Autodesk Fusion 360 part; units mm, degrees
(part 4 of 5)
sketch "Condenser contact rib sketch" plane through (0, 0, 1004) normal (0, 0, 1) x (1, 0, 0) in component "MM16 Upward-facing radiator panel"
  line L0 (-680, -282) -> (680, -282)
  line L1 (680, -282) -> (680, -258)
  line L2 (680, -258) -> (-680, -258)
  line L3 (-680, -258) -> (-680, -282)
extrude "Condenser contact rib" add sketch "Condenser contact rib sketch" along normal blind 14 bodies 194 in component "MM16 Upward-facing radiator panel"
ref_plane "WorkPlane7" through (-681, 0, 0) normal (1, 0, 0) x (0, 1, 0) in component "MM16 Upward-facing radiator panel"
sketch "Heat pipe contact groove sketch" plane through (-681, 0, 0) normal (1, 0, 0) x (0, 0, -1) in component "MM16 Upward-facing radiator panel"
  circle A0 centre (-1012, -270) radius 6
extrude "Heat pipe contact groove" cut sketch "Heat pipe contact groove sketch" along normal blind 1362 bodies 194 in component "MM16 Upward-facing radiator panel"
ref_plane "WorkPlane8" through (0, 0, 1004) normal (0, 0, 1) x (1, 0, 0) in component "MM16 Upward-facing radiator panel"
sketch "Condenser contact rib sketch (1)" plane through (0, 0, 1004) normal (0, 0, 1) x (1, 0, 0) in component "MM16 Upward-facing radiator panel"
  line L0 (-680, -102) -> (680, -102)
  line L1 (680, -102) -> (680, -78)
  line L2 (680, -78) -> (-680, -78)
  line L3 (-680, -78) -> (-680, -102)
extrude "Condenser contact rib (1)" add sketch "Condenser contact rib sketch (1)" along normal blind 14 bodies 194 in component "MM16 Upward-facing radiator panel"
ref_plane "WorkPlane9" through (-681, 0, 0) normal (1, 0, 0) x (0, 1, 0) in component "MM16 Upward-facing radiator panel"
sketch "Heat pipe contact groove sketch (1)" plane through (-681, 0, 0) normal (1, 0, 0) x (0, 0, -1) in component "MM16 Upward-facing radiator panel"
  circle A0 centre (-1012, -90) radius 6
extrude "Heat pipe contact groove (1)" cut sketch "Heat pipe contact groove sketch (1)" along normal blind 1362 bodies 194 in component "MM16 Upward-facing radiator panel"
ref_plane "WorkPlane10" through (0, 0, 1004) normal (0, 0, 1) x (1, 0, 0) in component "MM16 Upward-facing radiator panel"
sketch "Condenser contact rib sketch (2)" plane through (0, 0, 1004) normal (0, 0, 1) x (1, 0, 0) in component "MM16 Upward-facing radiator panel"
  line L0 (-680, 78) -> (680, 78)
  line L1 (680, 78) -> (680, 102)
  line L2 (680, 102) -> (-680, 102)
  line L3 (-680, 102) -> (-680, 78)
extrude "Condenser contact rib (2)" add sketch "Condenser contact rib sketch (2)" along normal blind 14 bodies 194 in component "MM16 Upward-facing radiator panel"
ref_plane "WorkPlane11" through (-681, 0, 0) normal (1, 0, 0) x (0, 1, 0) in component "MM16 Upward-facing radiator panel"
sketch "Heat pipe contact groove sketch (2)" plane through (-681, 0, 0) normal (1, 0, 0) x (0, 0, -1) in component "MM16 Upward-facing radiator panel"
  circle A0 centre (-1012, 90) radius 6
extrude "Heat pipe contact groove (2)" cut sketch "Heat pipe contact groove sketch (2)" along normal blind 1362 bodies 194 in component "MM16 Upward-facing radiator panel"
ref_plane "WorkPlane12" through (0, 0, 1004) normal (0, 0, 1) x (1, 0, 0) in component "MM16 Upward-facing radiator panel"
sketch "Condenser contact rib sketch (3)" plane through (0, 0, 1004) normal (0, 0, 1) x (1, 0, 0) in component "MM16 Upward-facing radiator panel"
  line L0 (-680, 258) -> (680, 258)
  line L1 (680, 258) -> (680, 282)
  line L2 (680, 282) -> (-680, 282)
  line L3 (-680, 282) -> (-680, 258)
extrude "Condenser contact rib (3)" add sketch "Condenser contact rib sketch (3)" along normal blind 14 bodies 194 in component "MM16 Upward-facing radiator panel"
ref_plane "WorkPlane13" through (-681, 0, 0) normal (1, 0, 0) x (0, 1, 0) in component "MM16 Upward-facing radiator panel"
sketch "Heat pipe contact groove sketch (3)" plane through (-681, 0, 0) normal (1, 0, 0) x (0, 0, -1) in component "MM16 Upward-facing radiator panel"
  circle A0 centre (-1012, 270) radius 6
extrude "Heat pipe contact groove (3)" cut sketch "Heat pipe contact groove sketch (3)" along normal blind 1362 bodies 194 in component "MM16 Upward-facing radiator panel"
ref_plane "WorkPlane14" through (0, 0, 1015) normal (0, 0, 1) x (1, 0, 0) in component "MM16 Upward-facing radiator panel"
sketch "Local fastener load spreader sketch" plane through (0, 0, 1015) normal (0, 0, 1) x (1, 0, 0) in component "MM16 Upward-facing radiator panel"
  line L0 (-680, -360) -> (-620, -360)
  line L1 (-620, -360) -> (-620, -300)
  line L2 (-620, -300) -> (-680, -300)
  line L3 (-680, -300) -> (-680, -360)
extrude "Local fastener load spreader" add sketch "Local fastener load spreader sketch" along normal blind 3 bodies 194 in component "MM16 Upward-facing radiator panel"
ref_plane "WorkPlane15" through (0, 0, 1015) normal (0, 0, 1) x (1, 0, 0) in component "MM16 Upward-facing radiator panel"
sketch "Local fastener load spreader sketch (1)" plane through (0, 0, 1015) normal (0, 0, 1) x (1, 0, 0) in component "MM16 Upward-facing radiator panel"
  line L0 (-680, 300) -> (-620, 300)
  line L1 (-620, 300) -> (-620, 360)
  line L2 (-620, 360) -> (-680, 360)
  line L3 (-680, 360) -> (-680, 300)
extrude "Local fastener load spreader (1)" add sketch "Local fastener load spreader sketch (1)" along normal blind 3 bodies 194 in component "MM16 Upward-facing radiator panel"
ref_plane "WorkPlane16" through (0, 0, 1015) normal (0, 0, 1) x (1, 0, 0) in component "MM16 Upward-facing radiator panel"
sketch "Local fastener load spreader sketch (2)" plane through (0, 0, 1015) normal (0, 0, 1) x (1, 0, 0) in component "MM16 Upward-facing radiator panel"
  line L0 (620, -360) -> (680, -360)
  line L1 (680, -360) -> (680, -300)
  line L2 (680, -300) -> (620, -300)
  line L3 (620, -300) -> (620, -360)
extrude "Local fastener load spreader (2)" add sketch "Local fastener load spreader sketch (2)" along normal blind 3 bodies 194 in component "MM16 Upward-facing radiator panel"
ref_plane "WorkPlane17" through (0, 0, 1015) normal (0, 0, 1) x (1, 0, 0) in component "MM16 Upward-facing radiator panel"
sketch "Local fastener load spreader sketch (3)" plane through (0, 0, 1015) normal (0, 0, 1) x (1, 0, 0) in component "MM16 Upward-facing radiator panel"
  line L0 (620, 300) -> (680, 300)
  line L1 (680, 300) -> (680, 360)
  line L2 (680, 360) -> (620, 360)
  line L3 (620, 360) -> (620, 300)
extrude "Local fastener load spreader (3)" add sketch "Local fastener load spreader sketch (3)" along normal blind 3 bodies 194 in component "MM16 Upward-facing radiator panel"
ref_plane "WorkPlane1" through (-672, 0, 0) normal (1, 0, 0) x (0, 1, 0) in component "MM46 Radiator four-standoff mounting set"
sketch "Sketch1" plane through (-672, 0, 0) normal (1, 0, 0) x (0, 0, -1) in component "MM46 Radiator four-standoff mounting set"
  arc A0 (-893.7271, -291.2934) -> (-864.9383, -368.0784) centre (0, 0) ccw
  arc A1 (-899.4317, -293.1527) -> (-870.4592, -370.4278) centre (0, 0) ccw
  line L0 (-893.7271, -291.2934) -> (-899.4317, -293.1527)
  line L1 (-864.9383, -368.0784) -> (-870.4592, -370.4278)
extrude "Conformal load-band foot" add sketch "Sketch1" along normal blind 44 separate body makes body 195 in component "MM46 Radiator four-standoff mounting set"
ref_plane "WorkPlane2" through (0, 0, 850) normal (0, 0, 1) x (1, 0, 0) in component "MM46 Radiator four-standoff mounting set"
sketch "Thin-wall support neck sketch" plane through (0, 0, 850) normal (0, 0, 1) x (1, 0, 0) in component "MM46 Radiator four-standoff mounting set"
  line L0 (-655, -338) -> (-645, -338)
  line L1 (-645, -338) -> (-645, -322)
  line L2 (-645, -322) -> (-655, -322)
  line L3 (-655, -322) -> (-655, -338)
  line L4 (-654.4, -337.4) -> (-645.6, -337.4)
  line L5 (-645.6, -337.4) -> (-645.6, -322.6)
  line L6 (-645.6, -322.6) -> (-654.4, -322.6)
  line L7 (-654.4, -322.6) -> (-654.4, -337.4)
extrude "Thin-wall support neck" add sketch "Thin-wall support neck sketch" along normal blind 159 bodies 195 in component "MM46 Radiator four-standoff mounting set"
ref_plane "WorkPlane3" through (0, 0, 1009) normal (0, 0, 1) x (1, 0, 0) in component "MM46 Radiator four-standoff mounting set"
sketch "Panel bearing flange sketch" plane through (0, 0, 1009) normal (0, 0, 1) x (1, 0, 0) in component "MM46 Radiator four-standoff mounting set"
  line L0 (-675, -355) -> (-625, -355)
  line L1 (-625, -355) -> (-625, -305)
  line L2 (-625, -305) -> (-675, -305)
  line L3 (-675, -305) -> (-675, -355)
extrude "Panel bearing flange" add sketch "Panel bearing flange sketch" along normal blind 6 bodies 195 in component "MM46 Radiator four-standoff mounting set"
ref_plane "WorkPlane7" through (0, 0, 865) normal (0, 0, 1) x (1, 0, 0) in component "MM07 MLI blanket envelope"
sketch "Radiator support blanket clearance sketch" plane through (0, 0, 865) normal (0, 0, 1) x (1, 0, 0) in component "MM07 MLI blanket envelope"
  line L0 (-677, -385) -> (-623, -385)
  line L1 (-623, -385) -> (-623, -275)
  line L2 (-623, -275) -> (-677, -275)
  line L3 (-677, -275) -> (-677, -385)
extrude "Radiator support blanket clearance" cut sketch "Radiator support blanket clearance sketch" along normal blind 160 bodies 13 in component "MM07 MLI blanket envelope"
ref_plane "WorkPlane4" through (-672, 0, 0) normal (1, 0, 0) x (0, 1, 0) in component "MM46 Radiator four-standoff mounting set"
sketch "Sketch4 (2)" plane through (-672, 0, 0) normal (1, 0, 0) x (0, 0, -1) in component "MM46 Radiator four-standoff mounting set"
  arc A0 (-864.9383, 368.0784) -> (-893.7271, 291.2934) centre (0, 0) ccw
  arc A1 (-870.4592, 370.4278) -> (-899.4317, 293.1527) centre (0, 0) ccw
  line L0 (-864.9383, 368.0784) -> (-870.4592, 370.4278)
  line L1 (-893.7271, 291.2934) -> (-899.4317, 293.1527)
extrude "Conformal load-band foot (1)" add sketch "Sketch4 (2)" along normal blind 44 separate body makes body 196 in component "MM46 Radiator four-standoff mounting set"
ref_plane "WorkPlane5" through (0, 0, 850) normal (0, 0, 1) x (1, 0, 0) in component "MM46 Radiator four-standoff mounting set"
sketch "Thin-wall support neck sketch (1)" plane through (0, 0, 850) normal (0, 0, 1) x (1, 0, 0) in component "MM46 Radiator four-standoff mounting set"
  line L0 (-655, 322) -> (-645, 322)
  line L1 (-645, 322) -> (-645, 338)
  line L2 (-645, 338) -> (-655, 338)
  line L3 (-655, 338) -> (-655, 322)
  line L4 (-654.4, 322.6) -> (-645.6, 322.6)
  line L5 (-645.6, 322.6) -> (-645.6, 337.4)
  line L6 (-645.6, 337.4) -> (-654.4, 337.4)
  line L7 (-654.4, 337.4) -> (-654.4, 322.6)
extrude "Thin-wall support neck (1)" add sketch "Thin-wall support neck sketch (1)" along normal blind 159 bodies 196 in component "MM46 Radiator four-standoff mounting set"
ref_plane "WorkPlane6" through (0, 0, 1009) normal (0, 0, 1) x (1, 0, 0) in component "MM46 Radiator four-standoff mounting set"
sketch "Panel bearing flange sketch (1)" plane through (0, 0, 1009) normal (0, 0, 1) x (1, 0, 0) in component "MM46 Radiator four-standoff mounting set"
  line L0 (-675, 305) -> (-625, 305)
  line L1 (-625, 305) -> (-625, 355)
  line L2 (-625, 355) -> (-675, 355)
  line L3 (-675, 355) -> (-675, 305)
extrude "Panel bearing flange (1)" add sketch "Panel bearing flange sketch (1)" along normal blind 6 bodies 196 in component "MM46 Radiator four-standoff mounting set"
ref_plane "WorkPlane8" through (0, 0, 865) normal (0, 0, 1) x (1, 0, 0) in component "MM07 MLI blanket envelope"
sketch "Radiator support blanket clearance sketch (1)" plane through (0, 0, 865) normal (0, 0, 1) x (1, 0, 0) in component "MM07 MLI blanket envelope"
  line L0 (-677, 275) -> (-623, 275)
  line L1 (-623, 275) -> (-623, 385)
  line L2 (-623, 385) -> (-677, 385)
  line L3 (-677, 385) -> (-677, 275)
extrude "Radiator support blanket clearance (1)" cut sketch "Radiator support blanket clearance sketch (1)" along normal blind 160 bodies 13 in component "MM07 MLI blanket envelope"
ref_plane "WorkPlane7" through (628, 0, 0) normal (1, 0, 0) x (0, 1, 0) in component "MM46 Radiator four-standoff mounting set"
sketch "Sketch7 (2)" plane through (628, 0, 0) normal (1, 0, 0) x (0, 0, -1) in component "MM46 Radiator four-standoff mounting set"
  arc A0 (-893.7271, -291.2934) -> (-864.9383, -368.0784) centre (0, 0) ccw
  arc A1 (-899.4317, -293.1527) -> (-870.4592, -370.4278) centre (0, 0) ccw
  line L0 (-893.7271, -291.2934) -> (-899.4317, -293.1527)
  line L1 (-864.9383, -368.0784) -> (-870.4592, -370.4278)
extrude "Conformal load-band foot (2)" add sketch "Sketch7 (2)" along normal blind 44 separate body makes body 197 in component "MM46 Radiator four-standoff mounting set"
ref_plane "WorkPlane8" through (0, 0, 850) normal (0, 0, 1) x (1, 0, 0) in component "MM46 Radiator four-standoff mounting set"
sketch "Thin-wall support neck sketch (2)" plane through (0, 0, 850) normal (0, 0, 1) x (1, 0, 0) in component "MM46 Radiator four-standoff mounting set"
  line L0 (645, -338) -> (655, -338)
  line L1 (655, -338) -> (655, -322)
  line L2 (655, -322) -> (645, -322)
  line L3 (645, -322) -> (645, -338)
  line L4 (645.6, -337.4) -> (654.4, -337.4)
  line L5 (654.4, -337.4) -> (654.4, -322.6)
  line L6 (654.4, -322.6) -> (645.6, -322.6)
  line L7 (645.6, -322.6) -> (645.6, -337.4)
extrude "Thin-wall support neck (2)" add sketch "Thin-wall support neck sketch (2)" along normal blind 159 bodies 197 in component "MM46 Radiator four-standoff mounting set"
ref_plane "WorkPlane9" through (0, 0, 1009) normal (0, 0, 1) x (1, 0, 0) in component "MM46 Radiator four-standoff mounting set"
sketch "Panel bearing flange sketch (2)" plane through (0, 0, 1009) normal (0, 0, 1) x (1, 0, 0) in component "MM46 Radiator four-standoff mounting set"
  line L0 (625, -355) -> (675, -355)
  line L1 (675, -355) -> (675, -305)
  line L2 (675, -305) -> (625, -305)
  line L3 (625, -305) -> (625, -355)
extrude "Panel bearing flange (2)" add sketch "Panel bearing flange sketch (2)" along normal blind 6 bodies 197 in component "MM46 Radiator four-standoff mounting set"
ref_plane "WorkPlane9" through (0, 0, 865) normal (0, 0, 1) x (1, 0, 0) in component "MM07 MLI blanket envelope"
sketch "Radiator support blanket clearance sketch (2)" plane through (0, 0, 865) normal (0, 0, 1) x (1, 0, 0) in component "MM07 MLI blanket envelope"
  line L0 (623, -385) -> (677, -385)
  line L1 (677, -385) -> (677, -275)
  line L2 (677, -275) -> (623, -275)
  line L3 (623, -275) -> (623, -385)
extrude "Radiator support blanket clearance (2)" cut sketch "Radiator support blanket clearance sketch (2)" along normal blind 160 bodies 13 in component "MM07 MLI blanket envelope"
ref_plane "WorkPlane10" through (628, 0, 0) normal (1, 0, 0) x (0, 1, 0) in component "MM46 Radiator four-standoff mounting set"
sketch "Sketch10 (2)" plane through (628, 0, 0) normal (1, 0, 0) x (0, 0, -1) in component "MM46 Radiator four-standoff mounting set"
  arc A0 (-864.9383, 368.0784) -> (-893.7271, 291.2934) centre (0, 0) ccw
  arc A1 (-870.4592, 370.4278) -> (-899.4317, 293.1527) centre (0, 0) ccw
  line L0 (-864.9383, 368.0784) -> (-870.4592, 370.4278)
  line L1 (-893.7271, 291.2934) -> (-899.4317, 293.1527)
extrude "Conformal load-band foot (3)" add sketch "Sketch10 (2)" along normal blind 44 separate body makes body 198 in component "MM46 Radiator four-standoff mounting set"
ref_plane "WorkPlane11" through (0, 0, 850) normal (0, 0, 1) x (1, 0, 0) in component "MM46 Radiator four-standoff mounting set"
sketch "Thin-wall support neck sketch (3)" plane through (0, 0, 850) normal (0, 0, 1) x (1, 0, 0) in component "MM46 Radiator four-standoff mounting set"
  line L0 (645, 322) -> (655, 322)
  line L1 (655, 322) -> (655, 338)
  line L2 (655, 338) -> (645, 338)
  line L3 (645, 338) -> (645, 322)
  line L4 (645.6, 322.6) -> (654.4, 322.6)
  line L5 (654.4, 322.6) -> (654.4, 337.4)
  line L6 (654.4, 337.4) -> (645.6, 337.4)
  line L7 (645.6, 337.4) -> (645.6, 322.6)
extrude "Thin-wall support neck (3)" add sketch "Thin-wall support neck sketch (3)" along normal blind 159 bodies 198 in component "MM46 Radiator four-standoff mounting set"
ref_plane "WorkPlane12" through (0, 0, 1009) normal (0, 0, 1) x (1, 0, 0) in component "MM46 Radiator four-standoff mounting set"
sketch "Panel bearing flange sketch (3)" plane through (0, 0, 1009) normal (0, 0, 1) x (1, 0, 0) in component "MM46 Radiator four-standoff mounting set"
  line L0 (625, 305) -> (675, 305)
  line L1 (675, 305) -> (675, 355)
  line L2 (675, 355) -> (625, 355)
  line L3 (625, 355) -> (625, 305)
extrude "Panel bearing flange (3)" add sketch "Panel bearing flange sketch (3)" along normal blind 6 bodies 198 in component "MM46 Radiator four-standoff mounting set"
ref_plane "WorkPlane10" through (0, 0, 865) normal (0, 0, 1) x (1, 0, 0) in component "MM07 MLI blanket envelope"
sketch "Radiator support blanket clearance sketch (3)" plane through (0, 0, 865) normal (0, 0, 1) x (1, 0, 0) in component "MM07 MLI blanket envelope"
  line L0 (623, 275) -> (677, 275)
  line L1 (677, 275) -> (677, 385)
  line L2 (677, 385) -> (623, 385)
  line L3 (623, 385) -> (623, 275)
extrude "Radiator support blanket clearance (3)" cut sketch "Radiator support blanket clearance sketch (3)" along normal blind 160 bodies 13 in component "MM07 MLI blanket envelope"
ref_plane "WorkPlane13" through (-700, 0, 0) normal (1, 0, 0) x (0, 1, 0) in component "MM46 Radiator four-standoff mounting set"
sketch "Bearing clearance to band outside sketch" plane through (-700, 0, 0) normal (1, 0, 0) x (0, 0, -1) in component "MM46 Radiator four-standoff mounting set"
  circle A0 centre (0, 0) radius 940
extrude "Bearing clearance to band outside" cut sketch "Bearing clearance to band outside sketch" along normal blind 1400 bodies 195 196 197 198 in component "MM46 Radiator four-standoff mounting set"
ref_plane "WorkPlane1" through (-750, 0, 0) normal (1, 0, 0) x (0, 1, 0) in component "MM17 Four regulated heat-pipe and collector sets"
sketch "Outer pressure-wall collector sketch" plane through (-750, 0, 0) normal (1, 0, 0) x (0, 0, -1) in component "MM17 Four regulated heat-pipe and collector sets"
  arc A0 (-899.3104, -207.7734) -> (-861.6419, -330.9112) centre (0, 0) ccw
  arc A1 (-900.7719, -208.1111) -> (-863.0422, -331.449) centre (0, 0) ccw
  line L0 (-899.3104, -207.7734) -> (-900.7719, -208.1111)
  line L1 (-861.6419, -330.9112) -> (-863.0422, -331.449)
extrude "Outer pressure-wall collector" add sketch "Outer pressure-wall collector sketch" along normal blind 60 separate body makes body 199 in component "MM17 Four regulated heat-pipe and collector sets"
ref_plane "WorkPlane2" through (0, -270, 0) normal (0, 1, 0) x (0, 0, 1) in component "MM17 Four regulated heat-pipe and collector sets"
sketch "Regulated heat pipe centreline" plane through (0, -270, 0) normal (0, 1, 0) x (1, 0, 0) in component "MM17 Four regulated heat-pipe and collector sets"
  line L0 (-720, -875.6262) -> (-720, -992)
  arc A0 (-720, -992) -> (-700, -1012) centre (-700, -992) ccw
  line L1 (-700, -1012) -> (710, -1012)
ref_plane "WorkPlane3" through (0, 0, 875.6262) normal (0, 0, 1) x (1, 0, 0) in component "MM17 Four regulated heat-pipe and collector sets"
sketch "Twelve millimetre heat pipe wall" plane through (0, 0, 875.6262) normal (0, 0, 1) x (1, 0, 0) in component "MM17 Four regulated heat-pipe and collector sets"
  circle A0 centre (-720, -270) radius 6
  circle A1 centre (-720, -270) radius 5.5
sweep "Closed heat pipe envelope" add profiles "Twelve millimetre heat pipe wall" path "Regulated heat pipe centreline" along L0 A0 L1 section 1 bodies 199 in component "MM17 Four regulated heat-pipe and collector sets"
ref_plane "WorkPlane4" through (709.5, 0, 0) normal (1, 0, 0) x (0, 1, 0) in component "MM17 Four regulated heat-pipe and collector sets"
sketch "Condenser end cap sketch" plane through (709.5, 0, 0) normal (1, 0, 0) x (0, 0, -1) in component "MM17 Four regulated heat-pipe and collector sets"
  circle A0 centre (-1012, -270) radius 6
extrude "Condenser end cap" add sketch "Condenser end cap sketch" along normal blind 0.5 separate body makes body 200 in component "MM17 Four regulated heat-pipe and collector sets"
ref_plane "WorkPlane5" through (0, 0, 990) normal (0, 0, 1) x (1, 0, 0) in component "MM17 Four regulated heat-pipe and collector sets"
sketch "Gas reservoir connecting neck sketch" plane through (0, 0, 990) normal (0, 0, 1) x (1, 0, 0) in component "MM17 Four regulated heat-pipe and collector sets"
  circle A0 centre (710, -270) radius 3.5
  circle A1 centre (710, -270) radius 2.5
extrude "Gas reservoir connecting neck" add sketch "Gas reservoir connecting neck sketch" along normal blind 22 bodies 200 in component "MM17 Four regulated heat-pipe and collector sets"
ref_plane "WorkPlane6" through (695, 0, 0) normal (1, 0, 0) x (0, 1, 0) in component "MM17 Four regulated heat-pipe and collector sets"
sketch "Control gas reservoir envelope sketch" plane through (695, 0, 0) normal (1, 0, 0) x (0, 0, -1) in component "MM17 Four regulated heat-pipe and collector sets"
  circle A0 centre (-990, -270) radius 10
  circle A1 centre (-990, -270) radius 9.5
extrude "Control gas reservoir envelope" add sketch "Control gas reservoir envelope sketch" along normal blind 30 bodies 200 in component "MM17 Four regulated heat-pipe and collector sets"
ref_plane "WorkPlane7" through (695, 0, 0) normal (1, 0, 0) x (0, 1, 0) in component "MM17 Four regulated heat-pipe and collector sets"
sketch "Reservoir end closure sketch" plane through (695, 0, 0) normal (1, 0, 0) x (0, 0, -1) in component "MM17 Four regulated heat-pipe and collector sets"
  circle A0 centre (-990, -270) radius 10
extrude "Reservoir end closure" add sketch "Reservoir end closure sketch" along normal blind 0.5 bodies 200 in component "MM17 Four regulated heat-pipe and collector sets"
ref_plane "WorkPlane8" through (724.5, 0, 0) normal (1, 0, 0) x (0, 1, 0) in component "MM17 Four regulated heat-pipe and collector sets"
sketch "Reservoir end closure sketch (1)" plane through (724.5, 0, 0) normal (1, 0, 0) x (0, 0, -1) in component "MM17 Four regulated heat-pipe and collector sets"
  circle A0 centre (-990, -270) radius 10
extrude "Reservoir end closure (1)" add sketch "Reservoir end closure sketch (1)" along normal blind 0.5 bodies 200 in component "MM17 Four regulated heat-pipe and collector sets"
ref_plane "WorkPlane11" through (0, 0, 872) normal (0, 0, 1) x (1, 0, 0) in component "MM07 MLI blanket envelope"
sketch "Thermal collector blanket clearance sketch" plane through (0, 0, 872) normal (0, 0, 1) x (1, 0, 0) in component "MM07 MLI blanket envelope"
  line L0 (-755, -350) -> (-685, -350)
  line L1 (-685, -350) -> (-685, -190)
  line L2 (-685, -190) -> (-755, -190)
  line L3 (-755, -190) -> (-755, -350)
extrude "Thermal collector blanket clearance" cut sketch "Thermal collector blanket clearance sketch" along normal blind 150 bodies 13 in component "MM07 MLI blanket envelope"
ref_plane "WorkPlane9" through (690, 0, 0) normal (1, 0, 0) x (0, 1, 0) in component "MM17 Four regulated heat-pipe and collector sets"
sketch "Outer pressure-wall collector sketch (1)" plane through (690, 0, 0) normal (1, 0, 0) x (0, 0, -1) in component "MM17 Four regulated heat-pipe and collector sets"
  arc A0 (-922.6421, -25.7024) -> (-910.0859, -153.8592) centre (0, 0) ccw
  arc A1 (-924.1415, -25.7441) -> (-911.5649, -154.1092) centre (0, 0) ccw
  line L0 (-922.6421, -25.7024) -> (-924.1415, -25.7441)
  line L1 (-910.0859, -153.8592) -> (-911.5649, -154.1092)
extrude "Outer pressure-wall collector (1)" add sketch "Outer pressure-wall collector sketch (1)" along normal blind 60 separate body makes body 201 in component "MM17 Four regulated heat-pipe and collector sets"
ref_plane "WorkPlane10" through (0, -90, 0) normal (0, 1, 0) x (0, 0, 1) in component "MM17 Four regulated heat-pipe and collector sets"
sketch "Regulated heat pipe centreline (1)" plane through (0, -90, 0) normal (0, 1, 0) x (1, 0, 0) in component "MM17 Four regulated heat-pipe and collector sets"
  line L0 (720, -911.6017) -> (720, -992)
  arc A0 (700, -1012) -> (720, -992) centre (700, -992) ccw
  line L1 (700, -1012) -> (-710, -1012)
ref_plane "WorkPlane11" through (0, 0, 911.6017) normal (0, 0, 1) x (1, 0, 0) in component "MM17 Four regulated heat-pipe and collector sets"
sketch "Twelve millimetre heat pipe wall (1)" plane through (0, 0, 911.6017) normal (0, 0, 1) x (1, 0, 0) in component "MM17 Four regulated heat-pipe and collector sets"
  circle A0 centre (720, -90) radius 6
  circle A1 centre (720, -90) radius 5.5
sweep "Closed heat pipe envelope (1)" add profiles "Twelve millimetre heat pipe wall (1)" path "Regulated heat pipe centreline (1)" along L0 A0 L1 section 1 bodies 201 in component "MM17 Four regulated heat-pipe and collector sets"
ref_plane "WorkPlane12" through (-710, 0, 0) normal (1, 0, 0) x (0, 1, 0) in component "MM17 Four regulated heat-pipe and collector sets"
sketch "Condenser end cap sketch (1)" plane through (-710, 0, 0) normal (1, 0, 0) x (0, 0, -1) in component "MM17 Four regulated heat-pipe and collector sets"
  circle A0 centre (-1012, -90) radius 6
extrude "Condenser end cap (1)" add sketch "Condenser end cap sketch (1)" along normal blind 0.5 separate body makes body 202 in component "MM17 Four regulated heat-pipe and collector sets"
ref_plane "WorkPlane13" through (0, 0, 990) normal (0, 0, 1) x (1, 0, 0) in component "MM17 Four regulated heat-pipe and collector sets"
sketch "Gas reservoir connecting neck sketch (1)" plane through (0, 0, 990) normal (0, 0, 1) x (1, 0, 0) in component "MM17 Four regulated heat-pipe and collector sets"
  circle A0 centre (-710, -90) radius 3.5
  circle A1 centre (-710, -90) radius 2.5
extrude "Gas reservoir connecting neck (1)" add sketch "Gas reservoir connecting neck sketch (1)" along normal blind 22 bodies 202 in component "MM17 Four regulated heat-pipe and collector sets"
ref_plane "WorkPlane14" through (-725, 0, 0) normal (1, 0, 0) x (0, 1, 0) in component "MM17 Four regulated heat-pipe and collector sets"
sketch "Control gas reservoir envelope sketch (1)" plane through (-725, 0, 0) normal (1, 0, 0) x (0, 0, -1) in component "MM17 Four regulated heat-pipe and collector sets"
  circle A0 centre (-990, -90) radius 10
  circle A1 centre (-990, -90) radius 9.5
extrude "Control gas reservoir envelope (1)" add sketch "Control gas reservoir envelope sketch (1)" along normal blind 30 bodies 202 in component "MM17 Four regulated heat-pipe and collector sets"
ref_plane "WorkPlane15" through (-725, 0, 0) normal (1, 0, 0) x (0, 1, 0) in component "MM17 Four regulated heat-pipe and collector sets"
sketch "Reservoir end closure sketch (2)" plane through (-725, 0, 0) normal (1, 0, 0) x (0, 0, -1) in component "MM17 Four regulated heat-pipe and collector sets"
  circle A0 centre (-990, -90) radius 10
extrude "Reservoir end closure (2)" add sketch "Reservoir end closure sketch (2)" along normal blind 0.5 bodies 202 in component "MM17 Four regulated heat-pipe and collector sets"
ref_plane "WorkPlane16" through (-695.5, 0, 0) normal (1, 0, 0) x (0, 1, 0) in component "MM17 Four regulated heat-pipe and collector sets"
sketch "Reservoir end closure sketch (3)" plane through (-695.5, 0, 0) normal (1, 0, 0) x (0, 0, -1) in component "MM17 Four regulated heat-pipe and collector sets"
  circle A0 centre (-990, -90) radius 10
extrude "Reservoir end closure (3)" add sketch "Reservoir end closure sketch (3)" along normal blind 0.5 bodies 202 in component "MM17 Four regulated heat-pipe and collector sets"
ref_plane "WorkPlane12" through (0, 0, 872) normal (0, 0, 1) x (1, 0, 0) in component "MM07 MLI blanket envelope"
sketch "Thermal collector blanket clearance sketch (1)" plane through (0, 0, 872) normal (0, 0, 1) x (1, 0, 0) in component "MM07 MLI blanket envelope"
  line L0 (685, -170) -> (755, -170)
  line L1 (755, -170) -> (755, -10)
  line L2 (755, -10) -> (685, -10)
  line L3 (685, -10) -> (685, -170)
extrude "Thermal collector blanket clearance (1)" cut sketch "Thermal collector blanket clearance sketch (1)" along normal blind 150 bodies 13 in component "MM07 MLI blanket envelope"
ref_plane "WorkPlane17" through (-750, 0, 0) normal (1, 0, 0) x (0, 1, 0) in component "MM17 Four regulated heat-pipe and collector sets"
sketch "Outer pressure-wall collector sketch (2)" plane through (-750, 0, 0) normal (1, 0, 0) x (0, 0, -1) in component "MM17 Four regulated heat-pipe and collector sets"
  arc A0 (-910.0859, 153.8592) -> (-922.6421, 25.7024) centre (0, 0) ccw
  arc A1 (-911.5649, 154.1092) -> (-924.1415, 25.7441) centre (0, 0) ccw
  line L0 (-910.0859, 153.8592) -> (-911.5649, 154.1092)
  line L1 (-922.6421, 25.7024) -> (-924.1415, 25.7441)
extrude "Outer pressure-wall collector (2)" add sketch "Outer pressure-wall collector sketch (2)" along normal blind 60 separate body makes body 203 in component "MM17 Four regulated heat-pipe and collector sets"
ref_plane "WorkPlane18" through (0, 90, 0) normal (0, 1, 0) x (0, 0, 1) in component "MM17 Four regulated heat-pipe and collector sets"
sketch "Regulated heat pipe centreline (2)" plane through (0, 90, 0) normal (0, 1, 0) x (1, 0, 0) in component "MM17 Four regulated heat-pipe and collector sets"
  line L0 (-720, -911.6017) -> (-720, -992)
  arc A0 (-720, -992) -> (-700, -1012) centre (-700, -992) ccw
  line L1 (-700, -1012) -> (710, -1012)
ref_plane "WorkPlane19" through (0, 0, 911.6017) normal (0, 0, 1) x (1, 0, 0) in component "MM17 Four regulated heat-pipe and collector sets"
sketch "Twelve millimetre heat pipe wall (2)" plane through (0, 0, 911.6017) normal (0, 0, 1) x (1, 0, 0) in component "MM17 Four regulated heat-pipe and collector sets"
  circle A0 centre (-720, 90) radius 6
  circle A1 centre (-720, 90) radius 5.5
sweep "Closed heat pipe envelope (2)" add profiles "Twelve millimetre heat pipe wall (2)" path "Regulated heat pipe centreline (2)" along L0 A0 L1 section 1 bodies 203 in component "MM17 Four regulated heat-pipe and collector sets"
ref_plane "WorkPlane20" through (709.5, 0, 0) normal (1, 0, 0) x (0, 1, 0) in component "MM17 Four regulated heat-pipe and collector sets"
sketch "Condenser end cap sketch (2)" plane through (709.5, 0, 0) normal (1, 0, 0) x (0, 0, -1) in component "MM17 Four regulated heat-pipe and collector sets"
  circle A0 centre (-1012, 90) radius 6
extrude "Condenser end cap (2)" add sketch "Condenser end cap sketch (2)" along normal blind 0.5 separate body makes body 204 in component "MM17 Four regulated heat-pipe and collector sets"
ref_plane "WorkPlane21" through (0, 0, 990) normal (0, 0, 1) x (1, 0, 0) in component "MM17 Four regulated heat-pipe and collector sets"
sketch "Gas reservoir connecting neck sketch (2)" plane through (0, 0, 990) normal (0, 0, 1) x (1, 0, 0) in component "MM17 Four regulated heat-pipe and collector sets"
  circle A0 centre (710, 90) radius 3.5
  circle A1 centre (710, 90) radius 2.5
extrude "Gas reservoir connecting neck (2)" add sketch "Gas reservoir connecting neck sketch (2)" along normal blind 22 bodies 204 in component "MM17 Four regulated heat-pipe and collector sets"
ref_plane "WorkPlane22" through (695, 0, 0) normal (1, 0, 0) x (0, 1, 0) in component "MM17 Four regulated heat-pipe and collector sets"
sketch "Control gas reservoir envelope sketch (2)" plane through (695, 0, 0) normal (1, 0, 0) x (0, 0, -1) in component "MM17 Four regulated heat-pipe and collector sets"
  circle A0 centre (-990, 90) radius 10
  circle A1 centre (-990, 90) radius 9.5
extrude "Control gas reservoir envelope (2)" add sketch "Control gas reservoir envelope sketch (2)" along normal blind 30 bodies 204 in component "MM17 Four regulated heat-pipe and collector sets"
ref_plane "WorkPlane23" through (695, 0, 0) normal (1, 0, 0) x (0, 1, 0) in component "MM17 Four regulated heat-pipe and collector sets"
sketch "Reservoir end closure sketch (4)" plane through (695, 0, 0) normal (1, 0, 0) x (0, 0, -1) in component "MM17 Four regulated heat-pipe and collector sets"
  circle A0 centre (-990, 90) radius 10
extrude "Reservoir end closure (4)" add sketch "Reservoir end closure sketch (4)" along normal blind 0.5 bodies 204 in component "MM17 Four regulated heat-pipe and collector sets"
ref_plane "WorkPlane24" through (724.5, 0, 0) normal (1, 0, 0) x (0, 1, 0) in component "MM17 Four regulated heat-pipe and collector sets"
sketch "Reservoir end closure sketch (5)" plane through (724.5, 0, 0) normal (1, 0, 0) x (0, 0, -1) in component "MM17 Four regulated heat-pipe and collector sets"
  circle A0 centre (-990, 90) radius 10
extrude "Reservoir end closure (5)" add sketch "Reservoir end closure sketch (5)" along normal blind 0.5 bodies 204 in component "MM17 Four regulated heat-pipe and collector sets"
ref_plane "WorkPlane13" through (0, 0, 872) normal (0, 0, 1) x (1, 0, 0) in component "MM07 MLI blanket envelope"
sketch "Thermal collector blanket clearance sketch (2)" plane through (0, 0, 872) normal (0, 0, 1) x (1, 0, 0) in component "MM07 MLI blanket envelope"
  line L0 (-755, 10) -> (-685, 10)
  line L1 (-685, 10) -> (-685, 170)
  line L2 (-685, 170) -> (-755, 170)
  line L3 (-755, 170) -> (-755, 10)
extrude "Thermal collector blanket clearance (2)" cut sketch "Thermal collector blanket clearance sketch (2)" along normal blind 150 bodies 13 in component "MM07 MLI blanket envelope"
ref_plane "WorkPlane25" through (690, 0, 0) normal (1, 0, 0) x (0, 1, 0) in component "MM17 Four regulated heat-pipe and collector sets"
sketch "Outer pressure-wall collector sketch (3)" plane through (690, 0, 0) normal (1, 0, 0) x (0, 0, -1) in component "MM17 Four regulated heat-pipe and collector sets"
  arc A0 (-861.6419, 330.9112) -> (-899.3104, 207.7734) centre (0, 0) ccw
  arc A1 (-863.0422, 331.449) -> (-900.7719, 208.1111) centre (0, 0) ccw
  line L0 (-861.6419, 330.9112) -> (-863.0422, 331.449)
  line L1 (-899.3104, 207.7734) -> (-900.7719, 208.1111)
extrude "Outer pressure-wall collector (3)" add sketch "Outer pressure-wall collector sketch (3)" along normal blind 60 separate body makes body 205 in component "MM17 Four regulated heat-pipe and collector sets"
ref_plane "WorkPlane26" through (0, 270, 0) normal (0, 1, 0) x (0, 0, 1) in component "MM17 Four regulated heat-pipe and collector sets"
sketch "Regulated heat pipe centreline (3)" plane through (0, 270, 0) normal (0, 1, 0) x (1, 0, 0) in component "MM17 Four regulated heat-pipe and collector sets"
  line L0 (720, -875.6262) -> (720, -992)
  arc A0 (700, -1012) -> (720, -992) centre (700, -992) ccw
  line L1 (700, -1012) -> (-710, -1012)
ref_plane "WorkPlane27" through (0, 0, 875.6262) normal (0, 0, 1) x (1, 0, 0) in component "MM17 Four regulated heat-pipe and collector sets"
sketch "Twelve millimetre heat pipe wall (3)" plane through (0, 0, 875.6262) normal (0, 0, 1) x (1, 0, 0) in component "MM17 Four regulated heat-pipe and collector sets"
  circle A0 centre (720, 270) radius 6
  circle A1 centre (720, 270) radius 5.5
sweep "Closed heat pipe envelope (3)" add profiles "Twelve millimetre heat pipe wall (3)" path "Regulated heat pipe centreline (3)" along L0 A0 L1 section 1 bodies 205 in component "MM17 Four regulated heat-pipe and collector sets"
ref_plane "WorkPlane28" through (-710, 0, 0) normal (1, 0, 0) x (0, 1, 0) in component "MM17 Four regulated heat-pipe and collector sets"
sketch "Condenser end cap sketch (3)" plane through (-710, 0, 0) normal (1, 0, 0) x (0, 0, -1) in component "MM17 Four regulated heat-pipe and collector sets"
  circle A0 centre (-1012, 270) radius 6
extrude "Condenser end cap (3)" add sketch "Condenser end cap sketch (3)" along normal blind 0.5 separate body makes body 206 in component "MM17 Four regulated heat-pipe and collector sets"
ref_plane "WorkPlane29" through (0, 0, 990) normal (0, 0, 1) x (1, 0, 0) in component "MM17 Four regulated heat-pipe and collector sets"
sketch "Gas reservoir connecting neck sketch (3)" plane through (0, 0, 990) normal (0, 0, 1) x (1, 0, 0) in component "MM17 Four regulated heat-pipe and collector sets"
  circle A0 centre (-710, 270) radius 3.5
  circle A1 centre (-710, 270) radius 2.5
extrude "Gas reservoir connecting neck (3)" add sketch "Gas reservoir connecting neck sketch (3)" along normal blind 22 bodies 206 in component "MM17 Four regulated heat-pipe and collector sets"
ref_plane "WorkPlane30" through (-725, 0, 0) normal (1, 0, 0) x (0, 1, 0) in component "MM17 Four regulated heat-pipe and collector sets"
sketch "Control gas reservoir envelope sketch (3)" plane through (-725, 0, 0) normal (1, 0, 0) x (0, 0, -1) in component "MM17 Four regulated heat-pipe and collector sets"
  circle A0 centre (-990, 270) radius 10
  circle A1 centre (-990, 270) radius 9.5
extrude "Control gas reservoir envelope (3)" add sketch "Control gas reservoir envelope sketch (3)" along normal blind 30 bodies 206 in component "MM17 Four regulated heat-pipe and collector sets"
ref_plane "WorkPlane31" through (-725, 0, 0) normal (1, 0, 0) x (0, 1, 0) in component "MM17 Four regulated heat-pipe and collector sets"
sketch "Reservoir end closure sketch (6)" plane through (-725, 0, 0) normal (1, 0, 0) x (0, 0, -1) in component "MM17 Four regulated heat-pipe and collector sets"
  circle A0 centre (-990, 270) radius 10
extrude "Reservoir end closure (6)" add sketch "Reservoir end closure sketch (6)" along normal blind 0.5 bodies 206 in component "MM17 Four regulated heat-pipe and collector sets"
ref_plane "WorkPlane32" through (-695.5, 0, 0) normal (1, 0, 0) x (0, 1, 0) in component "MM17 Four regulated heat-pipe and collector sets"
sketch "Reservoir end closure sketch (7)" plane through (-695.5, 0, 0) normal (1, 0, 0) x (0, 0, -1) in component "MM17 Four regulated heat-pipe and collector sets"
  circle A0 centre (-990, 270) radius 10
extrude "Reservoir end closure (7)" add sketch "Reservoir end closure sketch (7)" along normal blind 0.5 bodies 206 in component "MM17 Four regulated heat-pipe and collector sets"
ref_plane "WorkPlane14" through (0, 0, 872) normal (0, 0, 1) x (1, 0, 0) in component "MM07 MLI blanket envelope"
sketch "Thermal collector blanket clearance sketch (3)" plane through (0, 0, 872) normal (0, 0, 1) x (1, 0, 0) in component "MM07 MLI blanket envelope"
  line L0 (685, 190) -> (755, 190)
  line L1 (755, 190) -> (755, 350)
  line L2 (755, 350) -> (685, 350)
  line L3 (685, 350) -> (685, 190)
extrude "Thermal collector blanket clearance (3)" cut sketch "Thermal collector blanket clearance sketch (3)" along normal blind 150 bodies 13 in component "MM07 MLI blanket envelope"
ref_plane "WorkPlane33" through (-800, 0, 0) normal (1, 0, 0) x (0, 1, 0) in component "MM17 Four regulated heat-pipe and collector sets"
sketch "Pressure-wall outer clearance sketch" plane through (-800, 0, 0) normal (1, 0, 0) x (0, 0, -1) in component "MM17 Four regulated heat-pipe and collector sets"
  circle A0 centre (0, 0) radius 923
extrude "Pressure-wall outer clearance" cut sketch "Pressure-wall outer clearance sketch" along normal blind 1600 bodies 199 200 201 202 203 204 205 206 in component "MM17 Four regulated heat-pipe and collector sets"
ref_plane "WorkPlane34" through (-750, 0, 0) normal (1, 0, 0) x (0, 1, 0) in component "MM17 Four regulated heat-pipe and collector sets"
sketch "Inner heat collector on pressure wall sketch" plane through (-750, 0, 0) normal (1, 0, 0) x (0, 0, -1) in component "MM17 Four regulated heat-pipe and collector sets"
  arc A0 (-894.9259, -206.7604) -> (-857.4411, -329.2979) centre (0, 0) ccw
  arc A1 (-896.3874, -207.0981) -> (-858.8413, -329.8356) centre (0, 0) ccw
  line L0 (-894.9259, -206.7604) -> (-896.3874, -207.0981)
  line L1 (-857.4411, -329.2979) -> (-858.8413, -329.8356)
extrude "Inner heat collector on pressure wall" add sketch "Inner heat collector on pressure wall sketch" along normal blind 60 separate body makes body 207 in component "MM17 Four regulated heat-pipe and collector sets"
ref_plane "WorkPlane35" through (690, 0, 0) normal (1, 0, 0) x (0, 1, 0) in component "MM17 Four regulated heat-pipe and collector sets"
sketch "Inner heat collector on pressure wall sketch (1)" plane through (690, 0, 0) normal (1, 0, 0) x (0, 0, -1) in component "MM17 Four regulated heat-pipe and collector sets"
  arc A0 (-918.1438, -25.577) -> (-905.6489, -153.1091) centre (0, 0) ccw
  arc A1 (-919.6432, -25.6188) -> (-907.1279, -153.3591) centre (0, 0) ccw
  line L0 (-918.1438, -25.577) -> (-919.6432, -25.6188)
  line L1 (-905.6489, -153.1091) -> (-907.1279, -153.3591)
extrude "Inner heat collector on pressure wall (1)" add sketch "Inner heat collector on pressure wall sketch (1)" along normal blind 60 separate body makes body 208 in component "MM17 Four regulated heat-pipe and collector sets"
ref_plane "WorkPlane36" through (-750, 0, 0) normal (1, 0, 0) x (0, 1, 0) in component "MM17 Four regulated heat-pipe and collector sets"
sketch "Inner heat collector on pressure wall sketch (2)" plane through (-750, 0, 0) normal (1, 0, 0) x (0, 0, -1) in component "MM17 Four regulated heat-pipe and collector sets"
  arc A0 (-905.6489, 153.1091) -> (-918.1438, 25.577) centre (0, 0) ccw
  arc A1 (-907.1279, 153.3591) -> (-919.6432, 25.6188) centre (0, 0) ccw
  line L0 (-905.6489, 153.1091) -> (-907.1279, 153.3591)
  line L1 (-918.1438, 25.577) -> (-919.6432, 25.6188)
extrude "Inner heat collector on pressure wall (2)" add sketch "Inner heat collector on pressure wall sketch (2)" along normal blind 60 separate body makes body 209 in component "MM17 Four regulated heat-pipe and collector sets"
ref_plane "WorkPlane37" through (690, 0, 0) normal (1, 0, 0) x (0, 1, 0) in component "MM17 Four regulated heat-pipe and collector sets"
sketch "Inner heat collector on pressure wall sketch (3)" plane through (690, 0, 0) normal (1, 0, 0) x (0, 0, -1) in component "MM17 Four regulated heat-pipe and collector sets"
  arc A0 (-857.4411, 329.2979) -> (-894.9259, 206.7604) centre (0, 0) ccw
  arc A1 (-858.8413, 329.8356) -> (-896.3874, 207.0981) centre (0, 0) ccw
  line L0 (-857.4411, 329.2979) -> (-858.8413, 329.8356)
  line L1 (-894.9259, 206.7604) -> (-896.3874, 207.0981)
extrude "Inner heat collector on pressure wall (3)" add sketch "Inner heat collector on pressure wall sketch (3)" along normal blind 60 separate body makes body 210 in component "MM17 Four regulated heat-pipe and collector sets"
ref_plane "WorkPlane18" through (0, 0, 1000) normal (0, 0, 1) x (1, 0, 0) in component "MM16 Upward-facing radiator panel"
sketch "M6 panel mounting clearance sketch" plane through (0, 0, 1000) normal (0, 0, 1) x (1, 0, 0) in component "MM16 Upward-facing radiator panel"
  circle A0 centre (-664, -330) radius 3.25
extrude "M6 panel mounting clearance" cut sketch "M6 panel mounting clearance sketch" along normal blind 32 bodies 194 in component "MM16 Upward-facing radiator panel"
ref_plane "WorkPlane14" through (0, 0, 1000) normal (0, 0, 1) x (1, 0, 0) in component "MM46 Radiator four-standoff mounting set"
sketch "M6 panel mounting clearance sketch (2)" plane through (0, 0, 1000) normal (0, 0, 1) x (1, 0, 0) in component "MM46 Radiator four-standoff mounting set"
  circle A0 centre (-664, -330) radius 3.25
extrude "M6 panel mounting clearance'" cut sketch "M6 panel mounting clearance sketch (2)" along normal blind 32 bodies 195 196 197 198 in component "MM46 Radiator four-standoff mounting set"
ref_plane "WorkPlane1" through (0, 0, 1001) normal (0, 0, 1) x (1, 0, 0) in component "MM47 Radiator eight M6 fastener sets"
sketch "M6 nominal shank sketch" plane through (0, 0, 1001) normal (0, 0, 1) x (1, 0, 0) in component "MM47 Radiator eight M6 fastener sets"
  circle A0 centre (-664, -330) radius 3
extrude "M6 nominal shank" add sketch "M6 nominal shank sketch" along normal blind 20.2 separate body makes body 211 in component "MM47 Radiator eight M6 fastener sets"
ref_plane "WorkPlane2" through (0, 0, 1021.2) normal (0, 0, 1) x (1, 0, 0) in component "MM47 Radiator eight M6 fastener sets"
sketch "M6 hex head sketch" plane through (0, 0, 1021.2) normal (0, 0, 1) x (1, 0, 0) in component "MM47 Radiator eight M6 fastener sets"
  line L0 (-658.2265, -330) -> (-661.1132, -325)
  line L1 (-661.1132, -325) -> (-666.8868, -325)
  line L2 (-666.8868, -325) -> (-669.7735, -330)
  line L3 (-669.7735, -330) -> (-666.8868, -335)
  line L4 (-666.8868, -335) -> (-661.1132, -335)
  line L5 (-661.1132, -335) -> (-658.2265, -330)
extrude "M6 hex head" add sketch "M6 hex head sketch" along normal blind 4 bodies 211 in component "MM47 Radiator eight M6 fastener sets"
ref_plane "WorkPlane3" through (0, 0, 1020) normal (0, 0, 1) x (1, 0, 0) in component "MM47 Radiator eight M6 fastener sets"
sketch "M6 retaining washer sketch" plane through (0, 0, 1020) normal (0, 0, 1) x (1, 0, 0) in component "MM47 Radiator eight M6 fastener sets"
  circle A0 centre (-664, -330) radius 7
  circle A1 centre (-664, -330) radius 3.25
extrude "M6 retaining washer" add sketch "M6 retaining washer sketch" along normal blind 1.2 separate body makes body 212 in component "MM47 Radiator eight M6 fastener sets"
ref_plane "WorkPlane4" through (0, 0, 1003) normal (0, 0, 1) x (1, 0, 0) in component "MM47 Radiator eight M6 fastener sets"
sketch "M6 hex nut sketch" plane through (0, 0, 1003) normal (0, 0, 1) x (1, 0, 0) in component "MM47 Radiator eight M6 fastener sets"
  line L0 (-658.2265, -330) -> (-661.1132, -325)
  line L1 (-661.1132, -325) -> (-666.8868, -325)
  line L2 (-666.8868, -325) -> (-669.7735, -330)
  line L3 (-669.7735, -330) -> (-666.8868, -335)
  line L4 (-666.8868, -335) -> (-661.1132, -335)
  line L5 (-661.1132, -335) -> (-658.2265, -330)
  circle A0 centre (-664, -330) radius 3.25
extrude "M6 hex nut" add sketch "M6 hex nut sketch" along normal blind 6 separate body makes body 213 in component "MM47 Radiator eight M6 fastener sets"
ref_plane "WorkPlane19" through (0, 0, 1000) normal (0, 0, 1) x (1, 0, 0) in component "MM16 Upward-facing radiator panel"
sketch "M6 panel mounting clearance sketch (1)" plane through (0, 0, 1000) normal (0, 0, 1) x (1, 0, 0) in component "MM16 Upward-facing radiator panel"
  circle A0 centre (-636, -330) radius 3.25
extrude "M6 panel mounting clearance (1)" cut sketch "M6 panel mounting clearance sketch (1)" along normal blind 32 bodies 194 in component "MM16 Upward-facing radiator panel"
ref_plane "WorkPlane15" through (0, 0, 1000) normal (0, 0, 1) x (1, 0, 0) in component "MM46 Radiator four-standoff mounting set"
sketch "M6 panel mounting clearance sketch (1) (2)" plane through (0, 0, 1000) normal (0, 0, 1) x (1, 0, 0) in component "MM46 Radiator four-standoff mounting set"
  circle A0 centre (-636, -330) radius 3.25
extrude "M6 panel mounting clearance (1)'" cut sketch "M6 panel mounting clearance sketch (1) (2)" along normal blind 32 bodies 195 196 197 198 in component "MM46 Radiator four-standoff mounting set"
ref_plane "WorkPlane5" through (0, 0, 1001) normal (0, 0, 1) x (1, 0, 0) in component "MM47 Radiator eight M6 fastener sets"
sketch "M6 nominal shank sketch (1)" plane through (0, 0, 1001) normal (0, 0, 1) x (1, 0, 0) in component "MM47 Radiator eight M6 fastener sets"
  circle A0 centre (-636, -330) radius 3
extrude "M6 nominal shank (1)" add sketch "M6 nominal shank sketch (1)" along normal blind 20.2 separate body makes body 214 in component "MM47 Radiator eight M6 fastener sets"
ref_plane "WorkPlane6" through (0, 0, 1021.2) normal (0, 0, 1) x (1, 0, 0) in component "MM47 Radiator eight M6 fastener sets"
sketch "M6 hex head sketch (1)" plane through (0, 0, 1021.2) normal (0, 0, 1) x (1, 0, 0) in component "MM47 Radiator eight M6 fastener sets"
  line L0 (-630.2265, -330) -> (-633.1132, -325)
  line L1 (-633.1132, -325) -> (-638.8868, -325)
  line L2 (-638.8868, -325) -> (-641.7735, -330)
  line L3 (-641.7735, -330) -> (-638.8868, -335)
  line L4 (-638.8868, -335) -> (-633.1132, -335)
  line L5 (-633.1132, -335) -> (-630.2265, -330)
extrude "M6 hex head (1)" add sketch "M6 hex head sketch (1)" along normal blind 4 bodies 214 in component "MM47 Radiator eight M6 fastener sets"
ref_plane "WorkPlane7" through (0, 0, 1020) normal (0, 0, 1) x (1, 0, 0) in component "MM47 Radiator eight M6 fastener sets"
sketch "M6 retaining washer sketch (1)" plane through (0, 0, 1020) normal (0, 0, 1) x (1, 0, 0) in component "MM47 Radiator eight M6 fastener sets"
  circle A0 centre (-636, -330) radius 7
  circle A1 centre (-636, -330) radius 3.25
extrude "M6 retaining washer (1)" add sketch "M6 retaining washer sketch (1)" along normal blind 1.2 separate body makes body 215 in component "MM47 Radiator eight M6 fastener sets"
ref_plane "WorkPlane8" through (0, 0, 1003) normal (0, 0, 1) x (1, 0, 0) in component "MM47 Radiator eight M6 fastener sets"
sketch "M6 hex nut sketch (1)" plane through (0, 0, 1003) normal (0, 0, 1) x (1, 0, 0) in component "MM47 Radiator eight M6 fastener sets"
  line L0 (-630.2265, -330) -> (-633.1132, -325)
  line L1 (-633.1132, -325) -> (-638.8868, -325)
  line L2 (-638.8868, -325) -> (-641.7735, -330)
  line L3 (-641.7735, -330) -> (-638.8868, -335)
  line L4 (-638.8868, -335) -> (-633.1132, -335)
  line L5 (-633.1132, -335) -> (-630.2265, -330)
  circle A0 centre (-636, -330) radius 3.25
extrude "M6 hex nut (1)" add sketch "M6 hex nut sketch (1)" along normal blind 6 separate body makes body 216 in component "MM47 Radiator eight M6 fastener sets"
ref_plane "WorkPlane20" through (0, 0, 1000) normal (0, 0, 1) x (1, 0, 0) in component "MM16 Upward-facing radiator panel"
sketch "M6 panel mounting clearance sketch (2) (2)" plane through (0, 0, 1000) normal (0, 0, 1) x (1, 0, 0) in component "MM16 Upward-facing radiator panel"
  circle A0 centre (-664, 330) radius 3.25
extrude "M6 panel mounting clearance (2)" cut sketch "M6 panel mounting clearance sketch (2) (2)" along normal blind 32 bodies 194 in component "MM16 Upward-facing radiator panel"